Plotter5Bar_M4 (Autodesk Fusion 360 design; units mm, degrees)
Autodesk Fusion 360 part; units mm, degrees
(part 1 of 2)
sketch "Schizzo1" plane through (0, 0, 0) normal (0, 0, 1) x (1, 0, 0) in component "MotorMount"
  line L0 (-70, -26.15) -> (70, -26.15)
  line L1 (70, -26.15) -> (70, 26.15)
  line L2 (70, 26.15) -> (-70, 26.15)
  line L3 (-70, 26.15) -> (-70, -26.15)
  dimension "d77" = 70
  dimension "d78" = 26.15
  dimension "d79" = 70
  dimension "d80" = 26.15
  measures "d77" horizontal distance of origin L0.start
  measures "d78" vertical distance of origin L0.start
  measures "d79" horizontal distance of origin L1.end
  measures "d80" vertical distance of origin L1.end
extrude "Plate (1)" add sketch "Schizzo1" along normal blind 6 makes body 1 in component "MotorMount"
sketch "Schizzo2" plane through (0, 0, 0) normal (0, 0, 1) x (1, 0, 0) in component "MotorMount"
  circle A0 centre (-25, 0) radius 11.75
  circle A1 centre (-40.5, -15.5) radius 1.7
  circle A2 centre (-40.5, 15.5) radius 1.7
  circle A3 centre (-9.5, -15.5) radius 1.7
  circle A4 centre (-9.5, 15.5) radius 1.7
  circle A5 centre (25, 0) radius 11.75
  circle A6 centre (40.5, -15.5) radius 1.7
  circle A7 centre (40.5, 15.5) radius 1.7
  circle A8 centre (9.5, -15.5) radius 1.7
  circle A9 centre (9.5, 15.5) radius 1.7
  dimension "d83" = 25
  dimension "d84" = 23.5
  dimension "d85" = 40.5
  dimension "d86" = 15.5
  dimension "d87" = 3.4
  dimension "d88" = 40.5
  dimension "d89" = 15.5
  dimension "d90" = 3.4
  dimension "d91" = 9.5
  dimension "d92" = 15.5
  dimension "d93" = 3.4
  dimension "d94" = 9.5
  dimension "d95" = 15.5
  dimension "d96" = 3.4
  dimension "d97" = 25
  dimension "d98" = 23.5
  dimension "d99" = 40.5
  dimension "d100" = 15.5
  dimension "d101" = 3.4
  dimension "d102" = 40.5
  dimension "d103" = 15.5
  dimension "d104" = 3.4
  dimension "d105" = 9.5
  dimension "d106" = 15.5
  dimension "d107" = 3.4
  dimension "d108" = 9.5
  dimension "d109" = 15.5
  dimension "d110" = 3.4
  constraint horizontal origin A0.centre
  constraint horizontal origin A5.centre
  measures "d83" horizontal distance of origin A0.centre
  measures "d84" diameter of A0
  measures "d85" horizontal distance of origin A1.centre
  measures "d86" vertical distance of origin A1.centre
  measures "d87" diameter of A1
  measures "d88" horizontal distance of origin A2.centre
  measures "d89" vertical distance of origin A2.centre
  measures "d90" diameter of A2
  measures "d91" horizontal distance of origin A3.centre
  measures "d92" vertical distance of origin A3.centre
  measures "d93" diameter of A3
  measures "d94" horizontal distance of origin A4.centre
  measures "d95" vertical distance of origin A4.centre
  measures "d96" diameter of A4
  measures "d97" horizontal distance of origin A5.centre
  measures "d98" diameter of A5
  measures "d99" horizontal distance of origin A6.centre
  measures "d100" vertical distance of origin A6.centre
  measures "d101" diameter of A6
  measures "d102" horizontal distance of origin A7.centre
  measures "d103" vertical distance of origin A7.centre
  measures "d104" diameter of A7
  measures "d105" horizontal distance of origin A8.centre
  measures "d106" vertical distance of origin A8.centre
  measures "d107" diameter of A8
  measures "d108" horizontal distance of origin A9.centre
  measures "d109" vertical distance of origin A9.centre
  measures "d110" diameter of A9
extrude "MotorHoles (1)" cut sketch "Schizzo2" along normal blind 6 bodies 1 in component "MotorMount"
sketch "Schizzo3" plane through (0, 0, 0) normal (0, 0, 1) x (1, 0, 0) in component "MotorMount"
  circle A0 centre (-55, 0) radius 2.2
  circle A1 centre (-65, 0) radius 2.2
  circle A2 centre (55, 0) radius 2.2
  circle A3 centre (65, 0) radius 2.2
  dimension "d113" = 55
  dimension "d114" = 4.4
  dimension "d115" = 65
  dimension "d116" = 4.4
  dimension "d117" = 55
  dimension "d118" = 4.4
  dimension "d119" = 65
  dimension "d120" = 4.4
  constraint horizontal origin A0.centre
  constraint horizontal origin A1.centre
  constraint horizontal origin A2.centre
  constraint horizontal origin A3.centre
  measures "d113" horizontal distance of origin A0.centre
  measures "d114" diameter of A0
  measures "d115" horizontal distance of origin A1.centre
  measures "d116" diameter of A1
  measures "d117" horizontal distance of origin A2.centre
  measures "d118" diameter of A2
  measures "d119" horizontal distance of origin A3.centre
  measures "d120" diameter of A3
extrude "RailScrews (1)" cut sketch "Schizzo3" along normal blind 6 bodies 1 in component "MotorMount"
sketch "Schizzo4" plane through (0, 0, 0) normal (0, 0, 1) x (1, 0, 0) in component "MotorMount"
  circle A0 centre (-55, 0) radius 4
  circle A1 centre (-65, 0) radius 4
  circle A2 centre (55, 0) radius 4
  circle A3 centre (65, 0) radius 4
  dimension "d123" = 55
  dimension "d124" = 8
  dimension "d125" = 65
  dimension "d126" = 8
  dimension "d127" = 55
  dimension "d128" = 8
  dimension "d129" = 65
  dimension "d130" = 8
  constraint horizontal origin A0.centre
  constraint horizontal origin A1.centre
  constraint horizontal origin A2.centre
  constraint horizontal origin A3.centre
  measures "d123" horizontal distance of origin A0.centre
  measures "d124" diameter of A0
  measures "d125" horizontal distance of origin A1.centre
  measures "d126" diameter of A1
  measures "d127" horizontal distance of origin A2.centre
  measures "d128" diameter of A2
  measures "d129" horizontal distance of origin A3.centre
  measures "d130" diameter of A3
extrude "RailScrewCbore (1)" cut sketch "Schizzo4" along normal blind 4 from surface at 2 bodies 1 in component "MotorMount"
sketch "Schizzo5" plane through (0, 0, 0) normal (0, 0, 1) x (1, 0, 0) in component "MotorMount"
  line L0 (-52, -9) -> (-67, -9)
  line L1 (-67, -9) -> (-67, -22.15)
  line L2 (-67, -22.15) -> (-52, -22.15)
  line L3 (-52, -22.15) -> (-52, -9)
  line L4 (-52, 9) -> (-67, 9)
  line L5 (-67, 9) -> (-67, 22.15)
  line L6 (-67, 22.15) -> (-52, 22.15)
  line L7 (-52, 22.15) -> (-52, 9)
  line L8 (52, -9) -> (67, -9)
  line L9 (67, -9) -> (67, -22.15)
  line L10 (67, -22.15) -> (52, -22.15)
  line L11 (52, -22.15) -> (52, -9)
  line L12 (52, 9) -> (67, 9)
  line L13 (67, 9) -> (67, 22.15)
  line L14 (67, 22.15) -> (52, 22.15)
  line L15 (52, 22.15) -> (52, 9)
  dimension "d134" = 52
  dimension "d135" = 9
  dimension "d136" = 67
  dimension "d137" = 22.15
  dimension "d138" = 9
  dimension "d139" = 67
  dimension "d140" = 22.15
  dimension "d141" = 52
  dimension "d142" = 67
  dimension "d143" = 22.15
  dimension "d144" = 52
  dimension "d145" = 9
  dimension "d146" = 67
  dimension "d147" = 22.15
  measures "d134" horizontal distance of origin L0.start
  measures "d135" vertical distance of origin L0.start
  measures "d136" horizontal distance of origin L1.end
  measures "d137" vertical distance of origin L1.end
  measures "d138" vertical distance of origin L4.start
  measures "d139" horizontal distance of origin L5.end
  measures "d140" vertical distance of origin L5.end
  measures "d141" horizontal distance of origin L8.start
  measures "d142" horizontal distance of origin L9.end
  measures "d143" vertical distance of origin L9.end
  measures "d144" horizontal distance of origin L12.start
  measures "d145" vertical distance of origin L12.start
  measures "d146" horizontal distance of origin L13.end
  measures "d147" vertical distance of origin L13.end
extrude "Pockets (1)" cut sketch "Schizzo5" along normal blind 6 bodies 1 in component "MotorMount"
ref_plane "Piano di lavoro1" through (0, 0, 32.5) normal (0, 0, 1) x (1, 0, 0) in component "MotorMount"
sketch "Schizzo6" plane through (0, 0, 32.5) normal (0, 0, 1) x (1, 0, 0) in component "MotorMount"
  point P0 (-25, 0)
  point P1 (25, 0)
  dimension "d152" = 25
  dimension "d153" = 25
  constraint horizontal origin P0
  constraint horizontal origin P1
  measures "d152" horizontal distance of origin P0
  measures "d153" horizontal distance of origin P1
sketch "Schizzo1 (2)" plane through (0, 0, 0) normal (0, 0, 1) x (1, 0, 0) in component "PivotMount"
  line L0 (-70, 173.85) -> (70, 173.85)
  line L1 (70, 173.85) -> (70, 226.15)
  line L2 (70, 226.15) -> (-70, 226.15)
  line L3 (-70, 226.15) -> (-70, 173.85)
  dimension "d154" = 70
  dimension "d155" = 173.85
  dimension "d156" = 70
  dimension "d157" = 226.15
  measures "d154" horizontal distance of origin L0.start
  measures "d155" vertical distance of origin L0.start
  measures "d156" horizontal distance of origin L1.end
  measures "d157" vertical distance of origin L1.end
extrude "Plate (1)'" add sketch "Schizzo1 (2)" along normal blind 6 separate body makes body 2 in component "PivotMount"
sketch "Schizzo2 (2)" plane through (0, 0, 0) normal (0, 0, 1) x (1, 0, 0) in component "PivotMount"
  circle A0 centre (-25, 200) radius 15.25
  circle A1 centre (25, 200) radius 15.25
  dimension "d160" = 25
  dimension "d161" = 200
  dimension "d162" = 30.5
  dimension "d163" = 25
  dimension "d164" = 30.5
  measures "d160" horizontal distance of origin A0.centre
  measures "d161" vertical distance of origin A0.centre
  measures "d162" diameter of A0
  measures "d163" horizontal distance of origin A1.centre
  measures "d164" diameter of A1
extrude "Towers (1)" add sketch "Schizzo2 (2)" along normal blind 47 from surface at 6 bodies 2 in component "PivotMount"
sketch "Schizzo3 (2)" plane through (0, 0, 0) normal (0, 0, 1) x (1, 0, 0) in component "PivotMount"
  circle A0 centre (-25, 200) radius 12.25
  circle A1 centre (25, 200) radius 12.25
  dimension "d168" = 25
  dimension "d169" = 200
  dimension "d170" = 24.5
  dimension "d171" = 25
  dimension "d172" = 24.5
  measures "d168" horizontal distance of origin A0.centre
  measures "d169" vertical distance of origin A0.centre
  measures "d170" diameter of A0
  measures "d171" horizontal distance of origin A1.centre
  measures "d172" diameter of A1
extrude "BearingSeats (1)" cut sketch "Schizzo3 (2)" along normal blind 11 from surface at 42 bodies 2 in component "PivotMount"
sketch "Schizzo4 (2)" plane through (0, 0, 0) normal (0, 0, 1) x (1, 0, 0) in component "PivotMount"
  circle A0 centre (-25, 200) radius 5
  circle A1 centre (25, 200) radius 5
  dimension "d176" = 25
  dimension "d177" = 200
  dimension "d178" = 10
  dimension "d179" = 25
  dimension "d180" = 10
  measures "d176" horizontal distance of origin A0.centre
  measures "d177" vertical distance of origin A0.centre
  measures "d178" diameter of A0
  measures "d179" horizontal distance of origin A1.centre
  measures "d180" diameter of A1
extrude "AxleRelief (1)" cut sketch "Schizzo4 (2)" along normal blind 53 bodies 2 in component "PivotMount"
sketch "Schizzo5 (2)" plane through (0, 0, 0) normal (0, 0, 1) x (1, 0, 0) in component "PivotMount"
  circle A0 centre (-55, 200) radius 2.2
  circle A1 centre (-65, 200) radius 2.2
  circle A2 centre (55, 200) radius 2.2
  circle A3 centre (65, 200) radius 2.2
  dimension "d183" = 55
  dimension "d184" = 200
  dimension "d185" = 4.4
  dimension "d186" = 65
  dimension "d187" = 4.4
  dimension "d188" = 55
  dimension "d189" = 4.4
  dimension "d190" = 65
  dimension "d191" = 4.4
  measures "d183" horizontal distance of origin A0.centre
  measures "d184" vertical distance of origin A0.centre
  measures "d185" diameter of A0
  measures "d186" horizontal distance of origin A1.centre
  measures "d187" diameter of A1
  measures "d188" horizontal distance of origin A2.centre
  measures "d189" diameter of A2
  measures "d190" horizontal distance of origin A3.centre
  measures "d191" diameter of A3
extrude "RailScrews (1)'" cut sketch "Schizzo5 (2)" along normal blind 6 bodies 2 in component "PivotMount"
sketch "Schizzo6 (2)" plane through (0, 0, 0) normal (0, 0, 1) x (1, 0, 0) in component "PivotMount"
  circle A0 centre (-55, 200) radius 4
  circle A1 centre (-65, 200) radius 4
  circle A2 centre (55, 200) radius 4
  circle A3 centre (65, 200) radius 4
  dimension "d194" = 55
  dimension "d195" = 200
  dimension "d196" = 8
  dimension "d197" = 65
  dimension "d198" = 8
  dimension "d199" = 55
  dimension "d200" = 8
  dimension "d201" = 65
  dimension "d202" = 8
  measures "d194" horizontal distance of origin A0.centre
  measures "d195" vertical distance of origin A0.centre
  measures "d196" diameter of A0
  measures "d197" horizontal distance of origin A1.centre
  measures "d198" diameter of A1
  measures "d199" horizontal distance of origin A2.centre
  measures "d200" diameter of A2
  measures "d201" horizontal distance of origin A3.centre
  measures "d202" diameter of A3
extrude "RailScrewCbore (1)'" cut sketch "Schizzo6 (2)" along normal blind 4 from surface at 2 bodies 2 in component "PivotMount"
sketch "Schizzo7" plane through (0, 0, 0) normal (0, 0, 1) x (1, 0, 0) in component "PivotMount"
  line L0 (-52, 191) -> (-67, 191)
  line L1 (-67, 191) -> (-67, 177.85)
  line L2 (-67, 177.85) -> (-52, 177.85)
  line L3 (-52, 177.85) -> (-52, 191)
  line L4 (-52, 209) -> (-67, 209)
  line L5 (-67, 209) -> (-67, 222.15)
  line L6 (-67, 222.15) -> (-52, 222.15)
  line L7 (-52, 222.15) -> (-52, 209)
  line L8 (52, 191) -> (67, 191)
  line L9 (67, 191) -> (67, 177.85)
  line L10 (67, 177.85) -> (52, 177.85)
  line L11 (52, 177.85) -> (52, 191)
  line L12 (52, 209) -> (67, 209)
  line L13 (67, 209) -> (67, 222.15)
  line L14 (67, 222.15) -> (52, 222.15)
  line L15 (52, 222.15) -> (52, 209)
  dimension "d206" = 52
  dimension "d207" = 191
  dimension "d208" = 67
  dimension "d209" = 177.85
  dimension "d210" = 209
  dimension "d211" = 67
  dimension "d212" = 222.15
  dimension "d213" = 52
  dimension "d214" = 67
  dimension "d215" = 177.85
  dimension "d216" = 52
  dimension "d217" = 209
  dimension "d218" = 67
  dimension "d219" = 222.15
  measures "d206" horizontal distance of origin L0.start
  measures "d207" vertical distance of origin L0.start
  measures "d208" horizontal distance of origin L1.end
  measures "d209" vertical distance of origin L1.end
  measures "d210" vertical distance of origin L4.start
  measures "d211" horizontal distance of origin L5.end
  measures "d212" vertical distance of origin L5.end
  measures "d213" horizontal distance of origin L8.start
  measures "d214" horizontal distance of origin L9.end
  measures "d215" vertical distance of origin L9.end
  measures "d216" horizontal distance of origin L12.start
  measures "d217" vertical distance of origin L12.start
  measures "d218" horizontal distance of origin L13.end
  measures "d219" vertical distance of origin L13.end
extrude "Pockets (1)'" cut sketch "Schizzo7" along normal blind 6 bodies 2 in component "PivotMount"
ref_plane "Piano di lavoro1" through (0, 0, 46.5) normal (0, 0, 1) x (1, 0, 0) in component "PivotMount"
sketch "Schizzo8" plane through (0, 0, 46.5) normal (0, 0, 1) x (1, 0, 0) in component "PivotMount"
  point P0 (-25, 200)
  point P1 (25, 200)
  dimension "d224" = 25
  dimension "d225" = 200
  dimension "d226" = 25
  measures "d224" horizontal distance of origin P0
  measures "d225" vertical distance of origin P0
  measures "d226" horizontal distance of origin P1
sketch "Schizzo1 (3)" plane through (0, 0, 0) normal (0, 0, 1) x (1, 0, 0) in component "Rail"
  line L0 (122.5, -7.5) -> (137.5, -7.5)
  line L1 (137.5, -7.5) -> (137.5, 207.5)
  line L2 (137.5, 207.5) -> (122.5, 207.5)
  line L3 (122.5, 207.5) -> (122.5, -7.5)
  line L4 (50, -7.5) -> (130, -7.5)
  line L5 (130, -7.5) -> (130, 7.5)
  line L6 (130, 7.5) -> (50, 7.5)
  line L7 (50, 7.5) -> (50, -7.5)
  line L8 (50, 192.5) -> (130, 192.5)
  line L9 (130, 192.5) -> (130, 207.5)
  line L10 (130, 207.5) -> (50, 207.5)
  line L11 (50, 207.5) -> (50, 192.5)
  dimension "d227" = 122.5
  dimension "d228" = 7.5
  dimension "d229" = 137.5
  dimension "d230" = 207.5
  dimension "d231" = 50
  dimension "d232" = 130
  dimension "d233" = 7.5
  dimension "d234" = 50
  dimension "d235" = 192.5
  dimension "d236" = 130
  dimension "d237" = 207.5
  measures "d227" horizontal distance of origin L0.start
  measures "d228" vertical distance of origin L0.start
  measures "d229" horizontal distance of origin L1.end
  measures "d230" vertical distance of origin L1.end
  measures "d231" horizontal distance of origin L4.start
  measures "d232" horizontal distance of origin L5.end
  measures "d233" vertical distance of origin L5.end
  measures "d234" horizontal distance of origin L8.start
  measures "d235" vertical distance of origin L8.start
  measures "d236" horizontal distance of origin L9.end
  measures "d237" vertical distance of origin L9.end
extrude "Rail (1)" add sketch "Schizzo1 (3)" along normal blind 10 from surface at -10 separate body makes body 3 in component "Rail"
sketch "Schizzo2 (3)" plane through (0, 0, 0) normal (0, 0, 1) x (1, 0, 0) in component "Rail"
  line L0 (122.5, -7.5) -> (137.5, -7.5)
  line L1 (137.5, -7.5) -> (137.5, 7.5)
  line L2 (137.5, 7.5) -> (122.5, 7.5)
  line L3 (122.5, 7.5) -> (122.5, -7.5)
  line L4 (122.5, 192.5) -> (137.5, 192.5)
  line L5 (137.5, 192.5) -> (137.5, 207.5)
  line L6 (137.5, 207.5) -> (122.5, 207.5)
  line L7 (122.5, 207.5) -> (122.5, 192.5)
  dimension "d241" = 122.5
  dimension "d242" = 7.5
  dimension "d243" = 137.5
  dimension "d244" = 7.5
  dimension "d245" = 192.5
  dimension "d246" = 137.5
  dimension "d247" = 207.5
  measures "d241" horizontal distance of origin L0.start
  measures "d242" vertical distance of origin L0.start
  measures "d243" horizontal distance of origin L1.end
  measures "d244" vertical distance of origin L1.end
  measures "d245" vertical distance of origin L4.start
  measures "d246" horizontal distance of origin L5.end
  measures "d247" vertical distance of origin L5.end
extrude "Feet (1)" add sketch "Schizzo2 (3)" along normal blind 35 from surface at -45 bodies 3 in component "Rail"
sketch "Schizzo3 (3)" plane through (0, 0, 0) normal (0, 0, 1) x (1, 0, 0) in component "Rail"
  circle A0 centre (55, 0) radius 1.65
  circle A1 centre (65, 0) radius 1.65
  circle A2 centre (55, 200) radius 1.65
  circle A3 centre (65, 200) radius 1.65
  dimension "d251" = 55
  dimension "d252" = 3.3
  dimension "d253" = 65
  dimension "d254" = 3.3
  dimension "d255" = 200
  dimension "d256" = 3.3
  dimension "d257" = 65
  dimension "d258" = 200
  dimension "d259" = 3.3
  constraint horizontal origin A0.centre
  constraint horizontal origin A1.centre
  measures "d251" horizontal distance of origin A0.centre
  measures "d252" diameter of A0
  measures "d253" horizontal distance of origin A1.centre
  measures "d254" diameter of A1
  measures "d255" vertical distance of origin A2.centre
  measures "d256" diameter of A2
  measures "d257" horizontal distance of origin A3.centre
  measures "d258" vertical distance of origin A3.centre
  measures "d259" diameter of A3
extrude "PilotHoles (1)" cut sketch "Schizzo3 (3)" along normal blind 10 from surface at -10 bodies 3 in component "Rail"
sketch "Schizzo1 (4)" plane through (0, 0, 0) normal (0, 0, 1) x (1, 0, 0) in component "ProximalArm"
  line L0 (0, -6) -> (85, -6)
  line L1 (85, -6) -> (85, 6)
  line L2 (85, 6) -> (0, 6)
  line L3 (0, 6) -> (0, -6)
  dimension "d263" = 6
  dimension "d264" = 85
  dimension "d265" = 6
  constraint vertical origin L0.start
  measures "d263" vertical distance of origin L0.start
  measures "d264" horizontal distance of origin L1.end
  measures "d265" vertical distance of origin L1.end
extrude "Bar (1)" add sketch "Schizzo1 (4)" along normal blind 6 from surface at 19 separate body makes body 4 in component "ProximalArm"
sketch "Schizzo2 (4)" plane through (0, 0, 0) normal (0, 0, 1) x (1, 0, 0) in component "ProximalArm"
  circle A0 centre (0, 0) radius 10
  dimension "d269" = 20
  constraint vertical A0.centre origin
  constraint horizontal A0.centre origin
  measures "d269" diameter of A0
extrude "Hub (1)" add sketch "Schizzo2 (4)" along normal blind 18 from surface at 7 bodies 4 in component "ProximalArm"
sketch "Schizzo3 (4)" plane through (0, 0, 0) normal (0, 0, 1) x (1, 0, 0) in component "ProximalArm"
  circle A0 centre (85, 0) radius 15.25
  dimension "d273" = 85
  dimension "d274" = 30.5
  constraint horizontal origin A0.centre
  measures "d273" horizontal distance of origin A0.centre
  measures "d274" diameter of A0
extrude "ElbowBoss (1)" add sketch "Schizzo3 (4)" along normal blind 13 from surface at 12 bodies 4 in component "ProximalArm"
fillet "ArmFillets" radius 3 4 edges at (70.9799, 6, 22) (70.9799, -6, 22) (8, -6, 22) (8, 6, 22) on bodies 4 in component "ProximalArm"
sketch "Schizzo4 (3)" plane through (0, 0, 0) normal (0, 0, 1) x (1, 0, 0) in component "ProximalArm"
  circle A0 centre (0, 0) radius 2.6
  line L0 (-2, -1.6613) -> (-2, 1.6613)
  dimension "d280" = 5.2
  constraint vertical A0.centre origin
  constraint horizontal A0.centre origin
  measures "d280" diameter of A0
extrude "DBore (1)" cut sketch "Schizzo4 (3)" along normal blind 18 from surface at 7 contours A0 L0 picked at (-0.1511, 0.8737) bodies 4 in component "ProximalArm"
sketch "Schizzo5 (3)" plane through (0, 0, 0) normal (1, 0, 0) x (0, 0, -1) in component "ProximalArm"
  circle A0 centre (-16, 0) radius 1.65
extrude "GrubHole (1)" cut sketch "Schizzo5 (3)" against normal blind 11 bodies 4 in component "ProximalArm"
sketch "Schizzo6 (3)" plane through (0, 0, 0) normal (0, 0, 1) x (1, 0, 0) in component "ProximalArm"
  circle A0 centre (85, 0) radius 12.25
  dimension "d286" = 85
  dimension "d287" = 24.5
  constraint horizontal origin A0.centre
  measures "d286" horizontal distance of origin A0.centre
  measures "d287" diameter of A0
extrude "BearingSeat (1)" cut sketch "Schizzo6 (3)" along normal blind 11 from surface at 14 bodies 4 in component "ProximalArm"
sketch "Schizzo7 (2)" plane through (0, 0, 0) normal (0, 0, 1) x (1, 0, 0) in component "ProximalArm"
  circle A0 centre (85, 0) radius 5
  dimension "d291" = 85
  dimension "d292" = 10
  constraint horizontal origin A0.centre
  measures "d291" horizontal distance of origin A0.centre
  measures "d292" diameter of A0
extrude "AxleRelief (1)'" cut sketch "Schizzo7 (2)" along normal blind 15 from surface at 11 bodies 4 in component "ProximalArm"
ref_plane "Piano di lavoro1" through (0, 0, 32.5) normal (0, 0, 1) x (1, 0, 0) in component "ProximalArm"
sketch "Schizzo8 (2)" plane through (0, 0, 32.5) normal (0, 0, 1) x (1, 0, 0) in component "ProximalArm"
  point P0 (85, 0)
  dimension "d298" = 85
  constraint horizontal origin P0
  measures "d298" horizontal distance of origin P0
sketch "Schizzo1 (5)" plane through (0, 0, 0) normal (0, 0, 1) x (1, 0, 0) in component "DistalArm"
  line L0 (0, -6) -> (125, -6)
  line L1 (125, -6) -> (125, 6)
  line L2 (125, 6) -> (0, 6)
  line L3 (0, 6) -> (0, -6)
  dimension "d299" = 6
  dimension "d300" = 125
  dimension "d301" = 6
  constraint vertical origin L0.start
  measures "d299" vertical distance of origin L0.start
  measures "d300" horizontal distance of origin L1.end
  measures "d301" vertical distance of origin L1.end
extrude "Bar (1)'" add sketch "Schizzo1 (5)" along normal blind 6 from surface at 33.5 separate body makes body 5 in component "DistalArm"
sketch "Schizzo2 (5)" plane through (0, 0, 0) normal (0, 0, 1) x (1, 0, 0) in component "DistalArm"
  circle A0 centre (125, 0) radius 8
  dimension "d305" = 125
  dimension "d306" = 16
  constraint horizontal origin A0.centre
  measures "d305" horizontal distance of origin A0.centre
  measures "d306" diameter of A0
extrude "EffectorEye (1)" add sketch "Schizzo2 (5)" along normal blind 7 from surface at 32.5 bodies 5 in component "DistalArm"
sketch "Schizzo3 (5)" plane through (0, 0, 0) normal (0, 0, 1) x (1, 0, 0) in component "DistalArm"
  circle A0 centre (0, 0) radius 8
  dimension "d310" = 16
  constraint vertical A0.centre origin
  constraint horizontal A0.centre origin
  measures "d310" diameter of A0
extrude "ElbowEye (1)" add sketch "Schizzo3 (5)" along normal blind 14 from surface at 25.5 bodies 5 in component "DistalArm"
fillet "ArmFillets'" radius 3 4 edges at (5.2915, 6, 36.5) (5.2915, -6, 36.5) (119.7085, -6, 36.5) (119.7085, 6, 36.5) on bodies 5 in component "DistalArm"
sketch "Schizzo4 (4)" plane through (0, 0, 0) normal (0, 0, 1) x (1, 0, 0) in component "DistalArm"
  circle A0 centre (0, 0) radius 4.15
  circle A1 centre (125, 0) radius 4.15
  dimension "d316" = 8.3
  dimension "d317" = 125
  dimension "d318" = 8.3
  constraint vertical A0.centre origin
  constraint horizontal A0.centre origin
  constraint horizontal A0.centre A1.centre
  measures "d316" diameter of A0
  measures "d317" horizontal distance of A0.centre A1.centre
  measures "d318" diameter of A1
extrude "PinHoles (1)" cut sketch "Schizzo4 (4)" along normal blind 16 from surface at 25 bodies 5 in component "DistalArm"
sketch "Schizzo1 (6)" plane through (0, 0, 0) normal (0, 0, 1) x (1, 0, 0) in component "PassiveProximalArm"
  line L0 (0, -6) -> (85, -6)
  line L1 (85, -6) -> (85, 6)
  line L2 (85, 6) -> (0, 6)
  line L3 (0, 6) -> (0, -6)
  dimension "d322" = 6
  dimension "d323" = 85
  dimension "d324" = 6
  constraint vertical origin L0.start
  measures "d322" vertical distance of origin L0.start
  measures "d323" horizontal distance of origin L1.end
  measures "d324" vertical distance of origin L1.end
extrude "Bar (1)''" add sketch "Schizzo1 (6)" along normal blind 6 from surface at 54 separate body makes body 6 in component "PassiveProximalArm"
sketch "Schizzo2 (6)" plane through (0, 0, 0) normal (0, 0, 1) x (1, 0, 0) in component "PassiveProximalArm"
  circle A0 centre (0, 0) radius 8
  circle A1 centre (85, 0) radius 8
  dimension "d328" = 16
  dimension "d329" = 85
  dimension "d330" = 16
  constraint vertical A0.centre origin
  constraint horizontal A0.centre origin
  constraint horizontal A0.centre A1.centre
  measures "d328" diameter of A0
  measures "d329" horizontal distance of A0.centre A1.centre
  measures "d330" diameter of A1
extrude "Eyes (1)" add sketch "Schizzo2 (6)" along normal blind 6.5 from surface at 53.5 bodies 6 in component "PassiveProximalArm"
fillet "ArmFillets''" radius 3 4 edges at (79.7085, 6, 57) (79.7085, -6, 57) (5.2915, -6, 57) (5.2915, 6, 57) on bodies 6 in component "PassiveProximalArm"
sketch "Schizzo3 (6)" plane through (0, 0, 0) normal (0, 0, 1) x (1, 0, 0) in component "PassiveProximalArm"
  circle A0 centre (0, 0) radius 4
  dimension "d336" = 8
  constraint vertical A0.centre origin
  constraint horizontal A0.centre origin
  measures "d336" diameter of A0
extrude "BaseSpacer (1)" add sketch "Schizzo3 (6)" along normal blind 0.5 from surface at 53 bodies 6 in component "PassiveProximalArm"
sketch "Schizzo4 (5)" plane through (0, 0, 0) normal (0, 0, 1) x (1, 0, 0) in component "PassiveProximalArm"
  circle A0 centre (85, 0) radius 4
  dimension "d340" = 85
  dimension "d341" = 8
  constraint horizontal origin A0.centre
  measures "d340" horizontal distance of origin A0.centre
  measures "d341" diameter of A0
extrude "ElbowPin (1)" add sketch "Schizzo4 (5)" along normal blind 14.3 from surface at 39.2 bodies 6 in component "PassiveProximalArm"
sketch "Schizzo5 (4)" plane through (0, 0, 0) normal (0, 0, 1) x (1, 0, 0) in component "PassiveProximalArm"
  circle A0 centre (85, 0) radius 1.65
  dimension "d345" = 85
  dimension "d346" = 3.3
  constraint horizontal origin A0.centre
  measures "d345" horizontal distance of origin A0.centre
  measures "d346" diameter of A0
extrude "ElbowPinPilot (1)" cut sketch "Schizzo5 (4)" along normal blind 10 from surface at 39.2 bodies 6 in component "PassiveProximalArm"
sketch "Schizzo6 (4)" plane through (0, 0, 0) normal (0, 0, 1) x (1, 0, 0) in component "PassiveProximalArm"
  circle A0 centre (0, 0) radius 2.7
  dimension "d350" = 5.4
  constraint vertical A0.centre origin
  constraint horizontal A0.centre origin
  measures "d350" diameter of A0
extrude "AxleHole (1)" cut sketch "Schizzo6 (4)" along normal blind 9 from surface at 52 bodies 6 in component "PassiveProximalArm"
ref_plane "Piano di lavoro1" through (0, 0, 46.5) normal (0, 0, 1) x (1, 0, 0) in component "PassiveProximalArm"
sketch "Schizzo7 (3)" plane through (0, 0, 46.5) normal (0, 0, 1) x (1, 0, 0) in component "PassiveProximalArm"
  point P0 (85, 0)
  dimension "d356" = 85
  constraint horizontal origin P0
  measures "d356" horizontal distance of origin P0
sketch "Schizzo1 (7)" plane through (0, 0, 0) normal (0, 0, 1) x (1, 0, 0) in component "EffectorHub_SolenoidHolder"
  line L0 (-9.2, -10.2) -> (9.2, -10.2)
  line L1 (9.2, -10.2) -> (9.2, 10.2)
  line L2 (9.2, 10.2) -> (-9.2, 10.2)
  line L3 (-9.2, 10.2) -> (-9.2, -10.2)
  dimension "d357" = 9.2
  dimension "d358" = 10.2
  dimension "d359" = 9.2
  dimension "d360" = 10.2
  measures "d357" horizontal distance of origin L0.start
  measures "d358" vertical distance of origin L0.start
  measures "d359" horizontal distance of origin L1.end
  measures "d360" vertical distance of origin L1.end
extrude "Sleeve (1)" add sketch "Schizzo1 (7)" along normal blind 46 from surface at -27 separate body makes body 7 in component "EffectorHub_SolenoidHolder"
sketch "Schizzo2 (7)" plane through (0, 0, 0) normal (0, 0, 1) x (1, 0, 0) in component "EffectorHub_SolenoidHolder"
  circle A0 centre (0, 0) radius 8
  dimension "d364" = 16
  constraint vertical A0.centre origin
  constraint horizontal A0.centre origin
  measures "d364" diameter of A0
extrude "Collar (1)" add sketch "Schizzo2 (7)" along normal blind 6.5 from surface at 19 bodies 7 in component "EffectorHub_SolenoidHolder"
sketch "Schizzo3 (7)" plane through (0, 0, 0) normal (0, 0, 1) x (1, 0, 0) in component "EffectorHub_SolenoidHolder"
  circle A0 centre (0, 0) radius 4
  dimension "d368" = 8
  constraint vertical A0.centre origin
  constraint horizontal A0.centre origin
  measures "d368" diameter of A0
extrude "EffectorPin (1)" add sketch "Schizzo3 (7)" along normal blind 28.3 from surface at 25.5 bodies 7 in component "EffectorHub_SolenoidHolder"
sketch "Schizzo4 (6)" plane through (0, 0, 0) normal (0, 0, 1) x (1, 0, 0) in component "EffectorHub_SolenoidHolder"
  circle A0 centre (0, 0) radius 1.65
  dimension "d372" = 3.3
  constraint vertical A0.centre origin
  constraint horizontal A0.centre origin
  measures "d372" diameter of A0
extrude "EffectorPinPilot (1)" cut sketch "Schizzo4 (6)" along normal blind 10 from surface at 43.8 bodies 7 in component "EffectorHub_SolenoidHolder"
sketch "Schizzo5 (5)" plane through (0, 0, 0) normal (1, 0, 0) x (0, 0, -1) in component "EffectorHub_SolenoidHolder"
  circle A0 centre (12, 0) radius 5
extrude "ClampBoss (1)" add sketch "Schizzo5 (5)" against normal blind 15.2 bodies 7 in component "EffectorHub_SolenoidHolder"
sketch "Schizzo6 (5)" plane through (0, 0, 0) normal (0, 0, 1) x (1, 0, 0) in component "EffectorHub_SolenoidHolder"
  line L0 (-6.7, -7.7) -> (6.7, -7.7)
  line L1 (6.7, -7.7) -> (6.7, 7.7)
  line L2 (6.7, 7.7) -> (-6.7, 7.7)
  line L3 (-6.7, 7.7) -> (-6.7, -7.7)
  dimension "d378" = 6.7
  dimension "d379" = 7.7
  dimension "d380" = 6.7
  dimension "d381" = 7.7
  measures "d378" horizontal distance of origin L0.start
  measures "d379" vertical distance of origin L0.start
  measures "d380" horizontal distance of origin L1.end
  measures "d381" vertical distance of origin L1.end
extrude "SolenoidPocket (1)" cut sketch "Schizzo6 (5)" along normal blind 30 from surface at -27 bodies 7 in component "EffectorHub_SolenoidHolder"
sketch "Schizzo7 (4)" plane through (0, 0, 0) normal (0, 0, 1) x (1, 0, 0) in component "EffectorHub_SolenoidHolder"
  circle A0 centre (0, 0) radius 4
  dimension "d385" = 8
  constraint vertical A0.centre origin
  constraint horizontal A0.centre origin
  measures "d385" diameter of A0
extrude "PlungerRelief (1)" cut sketch "Schizzo7 (4)" along normal blind 10 from surface at 3 bodies 7 in component "EffectorHub_SolenoidHolder"
sketch "Schizzo8 (3)" plane through (0, 0, 0) normal (1, 0, 0) x (0, 0, -1) in component "EffectorHub_SolenoidHolder"
  circle A0 centre (12, 0) radius 1.65
extrude "ClampPilot (1)" cut sketch "Schizzo8 (3)" against normal blind 15.7 bodies 7 in component "EffectorHub_SolenoidHolder"
ref_plane "Piano di lavoro1" through (0, 0, 32.5) normal (0, 0, 1) x (1, 0, 0) in component "EffectorHub_SolenoidHolder"
sketch "Schizzo9" plane through (0, 0, 32.5) normal (0, 0, 1) x (1, 0, 0) in component "EffectorHub_SolenoidHolder"
ref_plane "Piano di lavoro2" through (0, 0, 46.5) normal (0, 0, 1) x (1, 0, 0) in component "EffectorHub_SolenoidHolder"
sketch "Schizzo10" plane through (0, 0, 46.5) normal (0, 0, 1) x (1, 0, 0) in component "EffectorHub_SolenoidHolder"
sketch "Schizzo1 (8)" plane through (0, 0, 0) normal (0, 0, 1) x (1, 0, 0) in component "M5Sleeve"
  circle A0 centre (0, 0) radius 4.9
  dimension "d395" = 9.8
  constraint vertical A0.centre origin
  constraint horizontal A0.centre origin
  measures "d395" diameter of A0
extrude "Flange (1)" add sketch "Schizzo1 (8)" along normal blind 0.5 from surface at 25 separate body makes body 8 in component "M5Sleeve"
sketch "Schizzo2 (8)" plane through (0, 0, 0) normal (0, 0, 1) x (1, 0, 0) in component "M5Sleeve"
  circle A0 centre (0, 0) radius 4
  dimension "d399" = 8
  constraint vertical A0.centre origin
  constraint horizontal A0.centre origin
  measures "d399" diameter of A0
extrude "Body (1)" add sketch "Schizzo2 (8)" along normal blind 14 from surface at 25.5 bodies 8 in component "M5Sleeve"
sketch "Schizzo3 (8)" plane through (0, 0, 0) normal (0, 0, 1) x (1, 0, 0) in component "M5Sleeve"
  circle A0 centre (0, 0) radius 2.7
  dimension "d403" = 5.4
  constraint vertical A0.centre origin
  constraint horizontal A0.centre origin
  measures "d403" diameter of A0
extrude "Bore (1)" cut sketch "Schizzo3 (8)" along normal blind 16 from surface at 24 bodies 8 in component "M5Sleeve"
sketch "Schizzo1 (9)" plane through (0, 0, 0) normal (0, 0, 1) x (1, 0, 0) in component "PinCap"
  circle A0 centre (0, 0) radius 7
  dimension "d407" = 14
  constraint vertical A0.centre origin
  constraint horizontal A0.centre origin
  measures "d407" diameter of A0
extrude "Cap (1)" add sketch "Schizzo1 (9)" along normal blind 2 separate body makes body 9 in component "PinCap"
sketch "Schizzo2 (9)" plane through (0, 0, 0) normal (0, 0, 1) x (1, 0, 0) in component "PinCap"
  circle A0 centre (0, 0) radius 2.2
  dimension "d410" = 4.4
  constraint vertical A0.centre origin
  constraint horizontal A0.centre origin
  measures "d410" diameter of A0
extrude "Hole (1)" cut sketch "Schizzo2 (9)" along normal blind 2 bodies 9 in component "PinCap"
sketch "Schizzo1 (10)" plane through (0, 0, 0) normal (0, 0, 1) x (1, 0, 0) in component "PURCHASED_NEMA17"
  line L0 (-21.15, -21.15) -> (21.15, -21.15)
  line L1 (21.15, -21.15) -> (21.15, 21.15)
  line L2 (21.15, 21.15) -> (-21.15, 21.15)
  line L3 (-21.15, 21.15) -> (-21.15, -21.15)
  dimension "d413" = 21.15
  dimension "d414" = 21.15
  dimension "d415" = 21.15
  dimension "d416" = 21.15
  measures "d413" horizontal distance of origin L0.start
  measures "d414" vertical distance of origin L0.start
  measures "d415" horizontal distance of origin L1.end
  measures "d416" vertical distance of origin L1.end
extrude "Body (1)'" add sketch "Schizzo1 (10)" along normal blind 40 from surface at -40 separate body makes body 10 in component "PURCHASED_NEMA17"
sketch "Schizzo2 (10)" plane through (0, 0, 0) normal (0, 0, 1) x (1, 0, 0) in component "PURCHASED_NEMA17"
  circle A0 centre (0, 0) radius 11.25
  dimension "d420" = 22.5
  constraint vertical A0.centre origin
  constraint horizontal A0.centre origin
  measures "d420" diameter of A0
extrude "Boss (1)" add sketch "Schizzo2 (10)" along normal blind 2 bodies 10 in component "PURCHASED_NEMA17"
sketch "Schizzo3 (9)" plane through (0, 0, 0) normal (0, 0, 1) x (1, 0, 0) in component "PURCHASED_NEMA17"
  circle A0 centre (0, 0) radius 2.5
  dimension "d423" = 5
  constraint vertical A0.centre origin
  constraint horizontal A0.centre origin
  measures "d423" diameter of A0
extrude "Shaft (1)" add sketch "Schizzo3 (9)" along normal blind 24 bodies 10 in component "PURCHASED_NEMA17"
sketch "Schizzo1 (11)" plane through (0, 0, 0) normal (0, 0, 1) x (1, 0, 0) in component "PURCHASED_Bearing"
  circle A0 centre (0, 0) radius 12.25
  circle A1 centre (0, 0) radius 2.5
  dimension "d426" = 24.5
  dimension "d427" = 5
  constraint vertical A0.centre A1.centre
  constraint horizontal A0.centre A1.centre
  measures "d426" diameter of A0
  measures "d427" diameter of A1
extrude "Ring (1)" add sketch "Schizzo1 (11)" along normal blind 11 separate body makes body 11 in component "PURCHASED_Bearing"
sketch "Schizzo1 (12)" plane through (0, 0, 0) normal (0, 0, 1) x (1, 0, 0) in component "PURCHASED_Solenoid_JF0530B"
  line L0 (-6.5, -7.5) -> (6.5, -7.5)
  line L1 (6.5, -7.5) -> (6.5, 7.5)
  line L2 (6.5, 7.5) -> (-6.5, 7.5)
  line L3 (-6.5, 7.5) -> (-6.5, -7.5)
  dimension "d430" = 6.5
  dimension "d431" = 7.5
  dimension "d432" = 6.5
  dimension "d433" = 7.5
  measures "d430" horizontal distance of origin L0.start
  measures "d431" vertical distance of origin L0.start
  measures "d432" horizontal distance of origin L1.end
  measures "d433" vertical distance of origin L1.end
extrude "Body (1)''" add sketch "Schizzo1 (12)" along normal blind 30 separate body makes body 12 in component "PURCHASED_Solenoid_JF0530B"
sketch "Schizzo2 (11)" plane through (0, 0, 0) normal (0, 0, 1) x (1, 0, 0) in component "PURCHASED_Solenoid_JF0530B"
  circle A0 centre (0, 0) radius 3
  dimension "d436" = 6
  constraint vertical A0.centre origin
  constraint horizontal A0.centre origin
  measures "d436" diameter of A0
extrude "Plunger (1)" add sketch "Schizzo2 (11)" along normal blind 38 from surface at -5 bodies 12 in component "PURCHASED_Solenoid_JF0530B"
sketch "Schizzo1 (13)" plane through (0, 0, 0) normal (0, 0, 1) x (1, 0, 0) in component "PURCHASED_M5x30"
  circle A0 centre (0, 0) radius 2.5
  dimension "d440" = 5
  constraint vertical A0.centre origin
  constraint horizontal A0.centre origin
  measures "d440" diameter of A0
extrude "Shank (1)" add sketch "Schizzo1 (13)" along normal blind 30 separate body makes body 13 in component "PURCHASED_M5x30"
sketch "Schizzo2 (12)" plane through (0, 0, 0) normal (0, 0, 1) x (1, 0, 0) in component "PURCHASED_M5x30"
  circle A0 centre (0, 0) radius 4.25
  dimension "d443" = 8.5
  constraint vertical A0.centre origin
  constraint horizontal A0.centre origin
  measures "d443" diameter of A0
extrude "Head (1)" add sketch "Schizzo2 (12)" along normal blind 5 from surface at -5 bodies 13 in component "PURCHASED_M5x30"
sketch "Schizzo1 (14)" plane through (0, 0, 0) normal (0, 0, 1) x (1, 0, 0) in component "PURCHASED_M5_Nut"
  line L0 (4, 2.3094) -> (0, 4.6188)
  line L1 (0, 4.6188) -> (-4, 2.3094)
  line L2 (-4, 2.3094) -> (-4, -2.3094)
  line L3 (-4, -2.3094) -> (0, -4.6188)
  line L4 (0, -4.6188) -> (4, -2.3094)
  line L5 (4, -2.3094) -> (4, 2.3094)
  circle A0 centre (0, 0) radius 2.7
  dimension "d447" = 5.4
  constraint vertical A0.centre origin
  constraint horizontal A0.centre origin
  measures "d447" diameter of A0
extrude "Nut (1)" add sketch "Schizzo1 (14)" along normal blind 4 separate body makes body 14 in component "PURCHASED_M5_Nut"
sketch "Schizzo1 (15)" plane through (0, 0, 0) normal (0, 0, 1) x (1, 0, 0) in component "PURCHASED_M4x9"
  circle A0 centre (0, 0) radius 2
  dimension "d450" = 4
  constraint vertical A0.centre origin
  constraint horizontal A0.centre origin
  measures "d450" diameter of A0
extrude "Shank (1)'" add sketch "Schizzo1 (15)" along normal blind 9 separate body makes body 15 in component "PURCHASED_M4x9"
sketch "Schizzo2 (13)" plane through (0, 0, 0) normal (0, 0, 1) x (1, 0, 0) in component "PURCHASED_M4x9"
  circle A0 centre (0, 0) radius 3.5
  dimension "d453" = 7
  constraint vertical A0.centre origin
  constraint horizontal A0.centre origin
  measures "d453" diameter of A0
extrude "Head (1)'" add sketch "Schizzo2 (13)" along normal blind 4 from surface at -4 bodies 15 in component "PURCHASED_M4x9"
sketch "Schizzo1 (16)" plane through (0, 0, 0) normal (0, 0, 1) x (1, 0, 0) in component "PencilHolder"
  circle A0 centre (0, 0) radius 5.775
  dimension "d478" = 11.55
  constraint vertical A0.centre origin
  constraint horizontal A0.centre origin
  measures "d478" diameter of A0
extrude "Clip (1)" add sketch "Schizzo1 (16)" along normal blind 40 from surface at -21 separate body makes body 16 in component "PencilHolder"
sketch "Schizzo2 (14)" plane through (0, 0, 0) normal (0, 0, 1) x (1, 0, 0) in component "PencilHolder"
  circle A0 centre (0, 0) radius 8
  dimension "d482" = 16
  constraint vertical A0.centre origin
  constraint horizontal A0.centre origin
  measures "d482" diameter of A0
extrude "Collar (1)'" add sketch "Schizzo2 (14)" along normal blind 6.5 from surface at 19 bodies 16 in component "PencilHolder"
sketch "Schizzo3 (10)" plane through (0, 0, 0) normal (0, 0, 1) x (1, 0, 0) in component "PencilHolder"
  circle A0 centre (0, 0) radius 3.9
  dimension "d486" = 7.8
  constraint vertical A0.centre origin
  constraint horizontal A0.centre origin
  measures "d486" diameter of A0
extrude "Pin (1)" add sketch "Schizzo3 (10)" along normal blind 28.3 from surface at 25.5 bodies 16 in component "PencilHolder"
sketch "Schizzo4 (7)" plane through (0, 0, 0) normal (0, 0, 1) x (1, 0, 0) in component "PencilHolder"
  circle A0 centre (0, 0) radius 1.65
  dimension "d490" = 3.3
  constraint vertical A0.centre origin
  constraint horizontal A0.centre origin
  measures "d490" diameter of A0
extrude "PinPilot" [suppressed] in component "PURCHASED_M4x9"
extrude "Estrusione4" cut sketch "Schizzo4 (7)" along normal blind 10 from surface at 43.8 bodies 16 in component "PencilHolder"
sketch "Schizzo5 (6)" plane through (0, 0, 0) normal (0, 0, 1) x (1, 0, 0) in component "PencilHolder"
  circle A0 centre (0, 0) radius 3.575
  dimension "d497" = 7.15
  constraint vertical A0.centre origin
  constraint horizontal A0.centre origin
  measures "d497" diameter of A0
extrude "Bore" [suppressed] in component "EffectorHub_SolenoidHolder"
extrude "Estrusione3" [no effect] in component "PURCHASED_Solenoid_JF0530B"
extrude "Estrusione5" cut sketch "Schizzo5 (6)" along normal blind 41 from surface at -22 bodies 16 in component "PencilHolder"
sketch "Schizzo6 (6)" plane through (0, 0, 0) normal (0, 0, 1) x (1, 0, 0) in component "PencilHolder"
  line L0 (0, -2.905) -> (11.4, -2.905)
  line L1 (11.4, -2.905) -> (11.4, 2.905)
  line L2 (11.4, 2.905) -> (0, 2.905)
  line L3 (0, 2.905) -> (0, -2.905)
  dimension "d507" = 2.905
  dimension "d508" = 11.4
  dimension "d509" = 2.905
  constraint vertical origin L0.start
  measures "d507" vertical distance of origin L0.start
  measures "d508" horizontal distance of origin L1.end
  measures "d509" vertical distance of origin L1.end
extrude "Mouth" [suppressed] in component "EffectorHub_SolenoidHolder"
extrude "Estrusione4'" [no effect] in component "PURCHASED_Solenoid_JF0530B"
extrude "Estrusione6" cut sketch "Schizzo6 (6)" along normal blind 41 from surface at -22 bodies 16 in component "PencilHolder"
fillet "MouthFillets" radius 0.6 4 edges at (2.0837, -2.905, -1) (4.9912, -2.905, -1) (2.0837, 2.905, -1) (4.9912, 2.905, -1) on bodies 16 in component "PencilHolder"
sketch "Schizzo1 (17)" plane through (0, 0, 0) normal (0, 0, 1) x (1, 0, 0) in component "SCENE_Desk"
  line L0 (-210, 90) -> (210, 90)
  line L1 (210, 90) -> (210, 290)
  line L2 (210, 290) -> (-210, 290)
  line L3 (-210, 290) -> (-210, 90)
  dimension "d521" = 210
  dimension "d522" = -90
  dimension "d523" = 210
  dimension "d524" = 290
  measures "d521" horizontal distance of origin L0.start
  measures "d522" vertical distance of origin L0.start
  measures "d523" horizontal distance of origin L1.end
  measures "d524" vertical distance of origin L1.end
extrude "Desk (1)" add sketch "Schizzo1 (17)" along normal blind 18 from surface at -63 separate body makes body 17 in component "SCENE_Desk"
sketch "Schizzo1 (18)" plane through (0, 0, 0) normal (0, 0, 1) x (1, 0, 0) in component "SCENE_Paper"
  line L0 (-105, 26) -> (105, 26)
  line L1 (105, 26) -> (105, 174)
  line L2 (105, 174) -> (-105, 174)
  line L3 (-105, 174) -> (-105, 26)
  dimension "d528" = 105
  dimension "d529" = 26
  dimension "d530" = 105
  dimension "d531" = 174
  measures "d528" horizontal distance of origin L0.start
  measures "d529" vertical distance of origin L0.start
  measures "d530" horizontal distance of origin L1.end
  measures "d531" vertical distance of origin L1.end
extrude "Paper (1)" add sketch "Schizzo1 (18)" along normal blind 0.1 from surface at -45 separate body makes body 18 in component "SCENE_Paper"
sketch "Schizzo1 (19)" plane through (0, 0, 0) normal (0, 0, 1) x (1, 0, 0) in component "SCENE_Pencil"
  circle A0 centre (0, 0) radius 3.5
  dimension "d535" = 7
  constraint vertical A0.centre origin
  constraint horizontal A0.centre origin
  measures "d535" diameter of A0
extrude "Body (1)'''" add sketch "Schizzo1 (19)" along normal blind 56.9 from surface at -37.9 separate body makes body 19 in component "SCENE_Pencil"
sketch "Schizzo2 (15)" plane through (0, 0, 0) normal (0, 1, 0) x (1, 0, 0) in component "SCENE_Pencil"
  line L0 (0, 44.9) -> (3.5, 37.9)
  line L1 (3.5, 37.9) -> (0, 37.9)
  line L2 (0, 37.9) -> (0, 44.9)
revolve "Rivoluzione1" add sketch "Schizzo2 (15)" angle 360 about axis through (0, 0, -37.9) along (0, 0, -1) bodies 19 in component "SCENE_Pencil"
ref_plane "Piano di lavoro1" through (0, 0, -44.85) normal (0, 0, 1) x (1, 0, 0)
sketch "Schizzo11" plane through (0, 0, 0) normal (0, 0, 1) x (1, 0, 0) in component "EffectorHub_SolenoidHolder"
  line L0 (0, -2.9) -> (10.2, -2.9)
  line L1 (10.2, -2.9) -> (10.2, 2.9)
  line L2 (10.2, 2.9) -> (0, 2.9)
  line L3 (0, 2.9) -> (0, -2.9)
  dimension "d555" = 2.9
  dimension "d556" = 10.2
  dimension "d557" = 2.9
  constraint vertical origin L0.start
  measures "d555" vertical distance of origin L0.start
  measures "d556" horizontal distance of origin L1.end
  measures "d557" vertical distance of origin L1.end
extrude "CableSlot (1)" cut sketch "Schizzo11" along normal blind 47 from surface at -28 bodies 7 in component "EffectorHub_SolenoidHolder"
component "MotorMount" placed x (1, 0, 0) y (0, 1, 0) z (0, 0, 1) at (0, 0, 0)
component "PivotMount" placed x (1, 0, 0) y (0, 1, 0) z (0, 0, 1) at (0, 0, 0)
component "Rail" placed x (1, 0, 0) y (0, 1, 0) z (0, 0, 1) at (0, 0, 0)
component "ProximalArm" placed x (-0.931494, 0.363756, 0) y (-0.363756, -0.931494, 0) z (0, 0, 1) at (-25, 0, 0)
component "DistalArm" placed x (0.833416, 0.552646, 0) y (0.552646, -0.833416, 0) z (0, 0, -1) at (-104.177, 30.9193, 65)
component "PassiveProximalArm" placed x (-0.931494, -0.363756, 0) y (0.363756, -0.931494, 0) z (0, 0, 1) at (-25, 200, 0)
component "EffectorHub_SolenoidHolder" placed x (1, 0, 0) y (0, 1, 0) z (0, 0, 1) at (0, 100, 0)
component "M5Sleeve" placed x (1, 0, 0) y (0, 1, 0) z (0, 0, 1) at (-104.177, 30.9193, 0)
component "PinCap" placed x (1, 0, 0) y (0, 1, 0) z (0, 0, 1) at (0, 100, 53.8)
component "PURCHASED_NEMA17" placed x (1, 0, 0) y (0, 1, 0) z (0, 0, 1) at (-25, 0, 0)
component "PURCHASED_Bearing" placed x (1, 0, 0) y (0, 1, 0) z (0, 0, 1) at (-104.177, 30.9193, 14)
component "PURCHASED_Solenoid_JF0530B" placed x (1, 0, 0) y (0, 1, 0) z (0, 0, 1) at (0, 100, -27)
component "PURCHASED_M5x30" placed x (1, 0, 0) y (0, 1, 0) z (0, 0, 1) at (-104.177, 30.9193, 14)
component "PURCHASED_M5_Nut" placed x (1, 0, 0) y (0, 1, 0) z (0, 0, 1) at (-104.177, 30.9193, 39.5)
component "PURCHASED_M4x9" placed x (1, 0, 0) y (0, -1, 0) z (0, 0, -1) at (0, 100, 55.8)
component "Rail" placed x (-1, 0, 0) y (0, -1, 0) z (0, 0, 1) at (0, 200, 0)
component "ProximalArm" placed x (0.931494, 0.363756, 0) y (-0.363756, 0.931494, 0) z (0, 0, 1) at (25, 0, 0)
component "DistalArm" placed x (-0.833416, 0.552646, 0) y (-0.552646, -0.833416, 0) z (0, 0, 1) at (104.177, 30.9193, 0)
component "DistalArm" placed x (0.833416, -0.552646, 0) y (0.552646, 0.833416, 0) z (0, 0, 1) at (-104.177, 169.0807, 14)
component "DistalArm" placed x (-0.833416, -0.552646, 0) y (-0.552646, 0.833416, 0) z (0, 0, -1) at (104.177, 169.0807, 79)
component "PassiveProximalArm" placed x (0.931494, -0.363756, 0) y (0.363756, 0.931494, 0) z (0, 0, 1) at (25, 200, 0)
component "M5Sleeve" placed x (1, 0, 0) y (0, 1, 0) z (0, 0, 1) at (104.177, 30.9193, 0)
component "PinCap" placed x (1, 0, 0) y (0, 1, 0) z (0, 0, 1) at (-104.177, 169.0807, 37.2)
component "PinCap" placed x (1, 0, 0) y (0, 1, 0) z (0, 0, 1) at (104.177, 169.0807, 37.2)
component "PURCHASED_NEMA17" placed x (1, 0, 0) y (0, 1, 0) z (0, 0, 1) at (25, 0, 0)
component "PURCHASED_Bearing" placed x (1, 0, 0) y (0, 1, 0) z (0, 0, 1) at (104.177, 30.9193, 14)
component "PURCHASED_Bearing" placed x (1, 0, 0) y (0, 1, 0) z (0, 0, 1) at (-25, 200, 42)
component "PURCHASED_Bearing" placed x (1, 0, 0) y (0, 1, 0) z (0, 0, 1) at (25, 200, 42)
component "PURCHASED_M5x30" placed x (1, 0, 0) y (0, 1, 0) z (0, 0, 1) at (104.177, 30.9193, 14)
component "PURCHASED_M5x30" placed x (1, 0, 0) y (0, 1, 0) z (0, 0, 1) at (-25, 200, 42)
component "PURCHASED_M5x30" placed x (1, 0, 0) y (0, 1, 0) z (0, 0, 1) at (25, 200, 42)
component "PURCHASED_M5_Nut" placed x (1, 0, 0) y (0, 1, 0) z (0, 0, 1) at (104.177, 30.9193, 39.5)
component "PURCHASED_M5_Nut" placed x (1, 0, 0) y (0, 1, 0) z (0, 0, 1) at (-25, 200, 60)
component "PURCHASED_M5_Nut" placed x (1, 0, 0) y (0, 1, 0) z (0, 0, 1) at (25, 200, 60)
component "PURCHASED_M4x9" placed x (1, 0, 0) y (0, 1, 0) z (0, 0, 1) at (-104.177, 169.0807, 37.2)
component "PURCHASED_M4x9" placed x (1, 0, 0) y (0, 1, 0) z (0, 0, 1) at (104.177, 169.0807, 37.2)
component "PURCHASED_M4x9" placed x (1, 0, 0) y (0, -1, 0) z (0, 0, -1) at (-55, 0, 2)